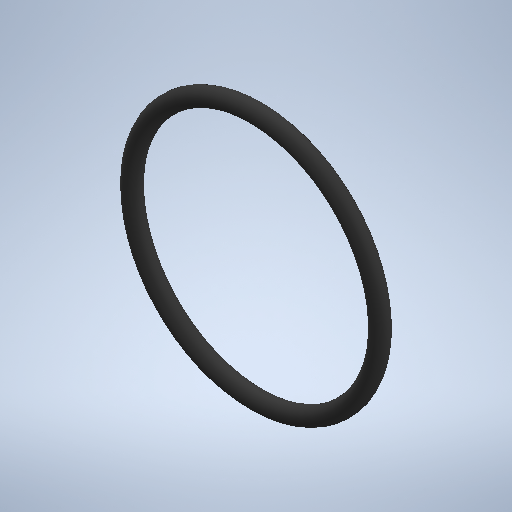
# Autodesk Inventor part: O-ring_D63
Saved by Autodesk Inventor 2025.3 (Build 293356000, 356)
## iProperties
Created: 2025-09-06
Part Number: O-ring_D63
Material: 一般
Document SubType Name: Modeling
Designer: daisuke
Density: 1 g/cm^3
Appearance: ゴム - 黒
Author: daisuke
Autodesk Inventor part; units mm, degrees
ref_plane "YZ Plane" through (0, 0, 0) normal (1, 0, 0) x (0, 1, 0)
ref_plane "XZ Plane" through (0, 0, 0) normal (0, 1, 0) x (-1, 0, 0)
ref_plane "XY Plane" through (0, 0, 0) normal (0, 0, 1) x (1, 0, 0)
sketch "スケッチ1" plane through (0, 0, 0) normal (0, 1, 0) x (-1, 0, 0)
  line L0 (0, 0) -> (-103.3594, 0) construction
  circle A0 centre (0, 0) radius 23.85 construction
  circle A1 centre (0, 0) radius 27.35 construction
  line L1 (-27.35, -14.3346) -> (-27.35, 14.3346) construction
  line L2 (-25.6, 17.2911) -> (-25.6, -17.2911) construction
  line L3 (-23.85, -14.4815) -> (-23.85, 14.4815) construction
  circle A2 centre (-25.6, 0) radius 1.75
  line L4 (0, -38.29) -> (0, 38.29) projected
  point P0 (-27.35, 0)
  point P1 (-23.85, 0)
  dimension "d0" = 47.7
  dimension "d1" = 54.7
  constraints: 8 end point, 3 centre point, 3 coincident, 3 midpoint, 3 point on line, 3 tangent, 2 vertical, 1 horizontal, 1 other
  measures "d0" diameter of A0
  measures "d1" diameter of A1
revolve "回転1" add sketch "スケッチ1" angle 360 about axis through (0, 0, -10) along (0, 0, 1)
